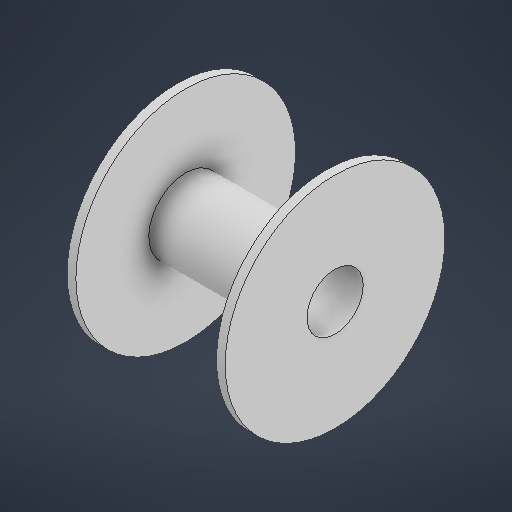
# Autodesk Inventor part: Tensioner
Saved by Autodesk Inventor 2026.3 (Build 303398000, 398)
## iProperties
Created: 2026-09-15
Part Number: Tensioner
Material: Generic
Document SubType Name: Modeling
Designer: grady
Density: 1 g/cm^3
Appearance: Default
Author: grady
Autodesk Inventor part; units mm, degrees
ref_plane "YZ Plane" through (0, 0, 0) normal (1, 0, 0) x (0, 1, 0)
ref_plane "XZ Plane" through (0, 0, 0) normal (0, 1, 0) x (-1, 0, 0)
ref_plane "XY Plane" through (0, 0, 0) normal (0, 0, 1) x (1, 0, 0)
sketch "Sketch1" plane through (0, 0, 0) normal (1, 0, 0) x (0, 1, 0)
  circle A0 centre (0, 0) radius 3.2
  circle A1 centre (0, 0) radius 12.5
  dimension "d0" = 6.4
  dimension "d1" = 25
  constraints: 2 centre point, 2 coincident
  measures "d0" diameter of A0
  measures "d1" diameter of A1
extrude "Extrusion1" add sketch "Sketch1" along normal blind 18
shell "Shell1" thickness 1 removed faces 1 at (12, 12.4595, -1.0058)
body "Solid1"
